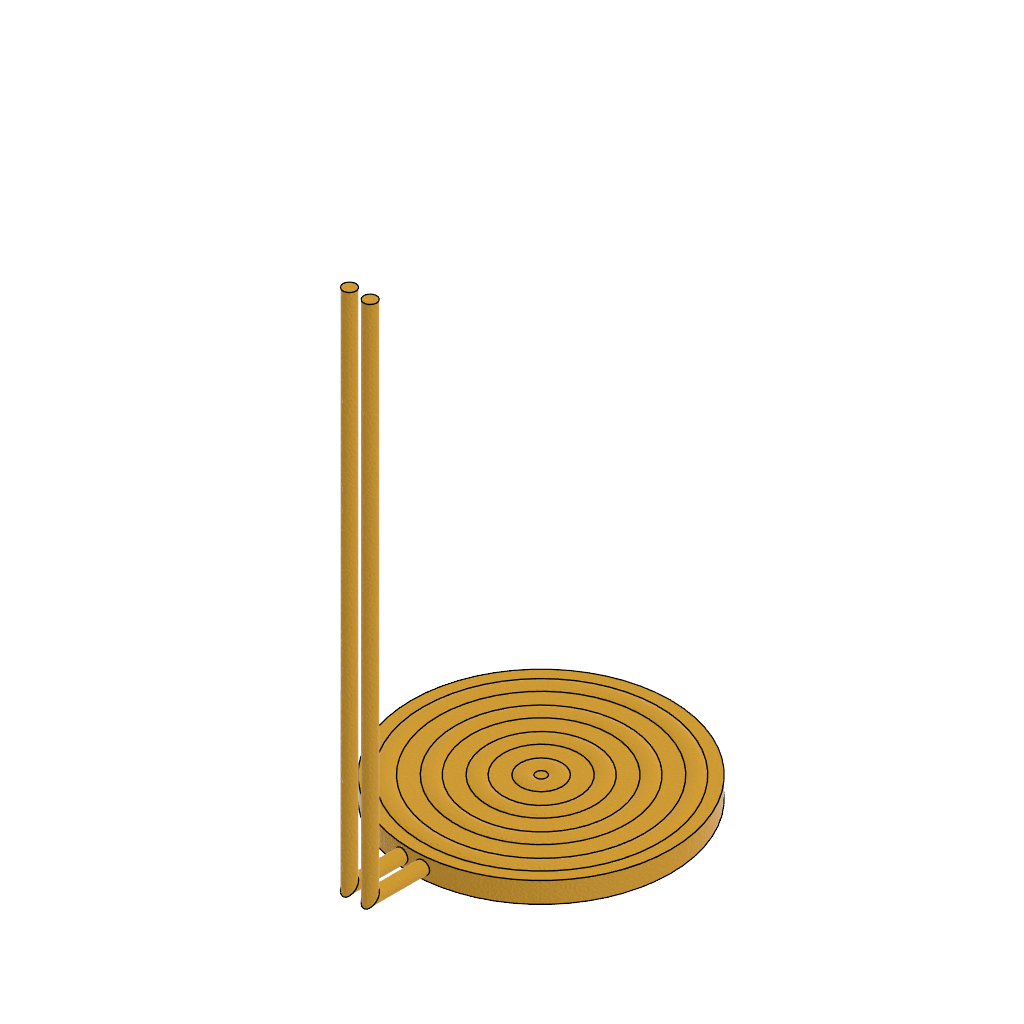
05-07 Heater element Placeholder (Autodesk Fusion 360 design; units mm, degrees)
Autodesk Fusion 360 part; units mm, degrees
sketch "Sketch1" plane through (0, 0, 0) normal (0, 0, 1) x (1, 0, 0)
  circle A0 centre (0, 0) radius 10
  dimension "d1" = 20
  constraint coincident A0.centre origin
  measures "d1" diameter of A0
extrude "Extrude1" add sketch "Sketch1" along normal blind 1.6
sketch "Sketch2" plane through (0, 0, 0) normal (0, 1, 0) x (1, 0, 0)
  circle A0 centre (1, -0.8) radius 1
  circle A1 centre (3.5, -0.8) radius 1
  circle A2 centre (6, -0.8) radius 1
  line L0 (-10, 0) -> (10, 0)
  circle A3 centre (8.5, -0.8) radius 1
  dimension "d4" = 2
  dimension "d5" = 1
  dimension "d6" = 0.8
  dimension "d7" = 2.5
  dimension "d8" = 2.5
  dimension "d9" = 2
  dimension "d10" = 2.5
  constraint horizontal A0.centre A1.centre
  constraint horizontal A0.centre A2.centre
  constraint equal A0 A1
  constraint equal A0 A2
  constraint horizontal A2.centre A3.centre
  measures "d4" diameter of A0
  measures "d5" horizontal distance of origin A0.centre
  measures "d6" distance of A0.centre L0
  measures "d7" distance of A0.centre A1.centre
  measures "d8" distance of A1.centre A2.centre
  measures "d9" diameter of A3
  measures "d10" horizontal distance of A2.centre A3.centre
revolve "Revolve1" add sketch "Sketch2" angle 360 about axis through (0, 0, 1.75) along (0, 0, 1)
sketch "Sketch3" plane through (0, 0, 0) normal (0, 1, 0) x (1, 0, 0)
  circle A0 centre (0.8, -0.8) radius 0.5
  circle A1 centre (-0.8, -0.8) radius 0.5
  line L0 (-10, -1.6) -> (10, -1.6)
  dimension "d12" = 1
  dimension "d13" = 0.8
  dimension "d14" = 0.8
  dimension "d15" = 1.6
  constraint horizontal A0.centre A1.centre
  constraint equal A0 A1
  measures "d12" diameter of A0
  measures "d13" horizontal distance of origin A0.centre
  measures "d14" distance of A0.centre L0
  measures "d15" distance of A0.centre A1.centre
sketch "Sketch4" plane through (0, 0, 0) normal (1, 0, 0) x (0, 1, 0)
  line L0 (0, 0.8) -> (-14, 0.8)
  line L1 (-14, 0.8) -> (-14, 40.8)
  dimension "d16" = 14
  dimension "d17" = 40
  dimension "d18" = 0.8
  constraint horizontal L0
  constraint perpendicular L0 L1
  measures "d16" distance of L0.start L0.end
  measures "d17" distance of L0.end L1.end
  measures "d18" distance of L0 origin
sweep "Sweep1" add profiles "Sketch3" path "Sketch4" along L0 L1 section 1
